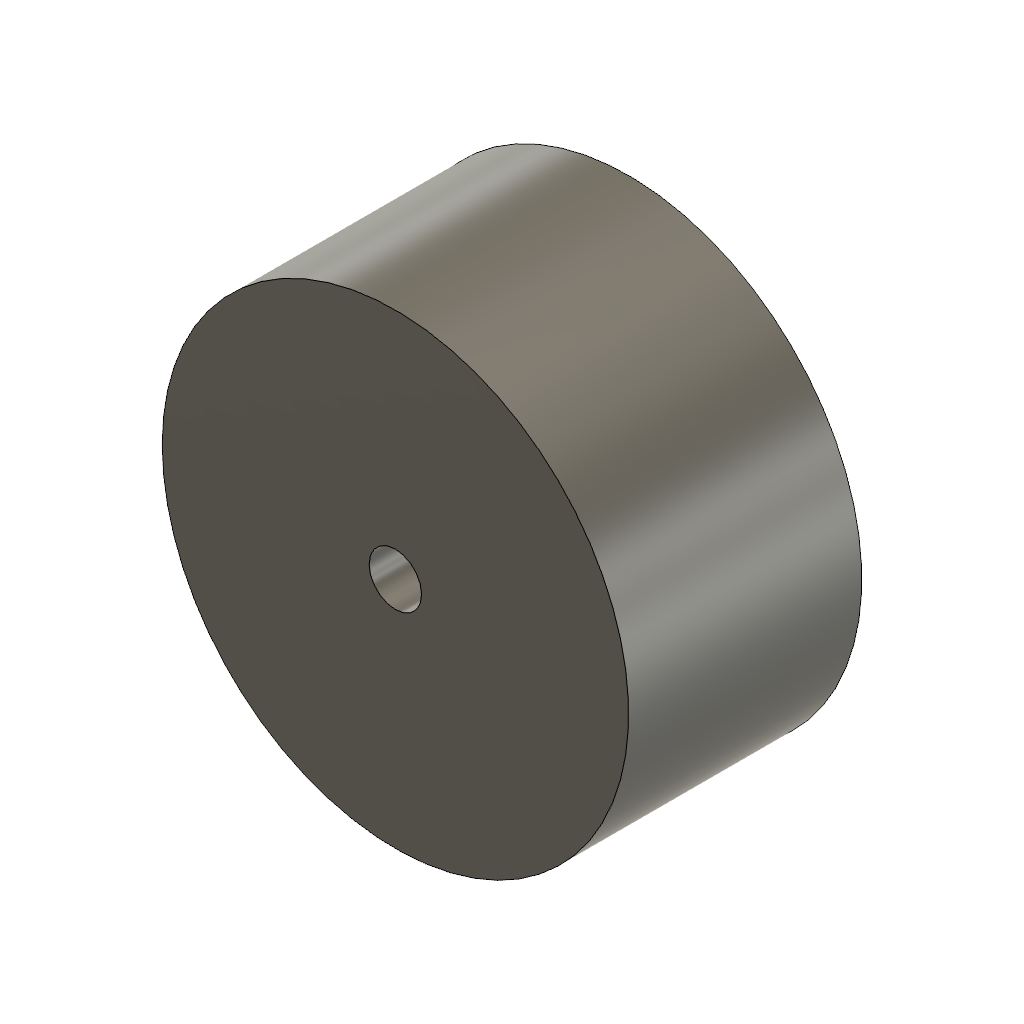
center_edge (Autodesk Fusion 360 design; units mm, degrees)
part number: 2026-10-20-19-38-30-570
Autodesk Fusion 360 part; units mm, degrees
sketch "Sketch1" plane through (0, 0, 0) normal (0, 0, 1) x (1, 0, 0)
  circle A0 centre (30, 20) radius 20
extrude "Extrude1" add sketch "Sketch1" along normal blind 20
hole "ProbeHolePlacement" at (30, 20, 20) direction (0, 0, -1) diameter 4.5 depth 11 tip angle 118
